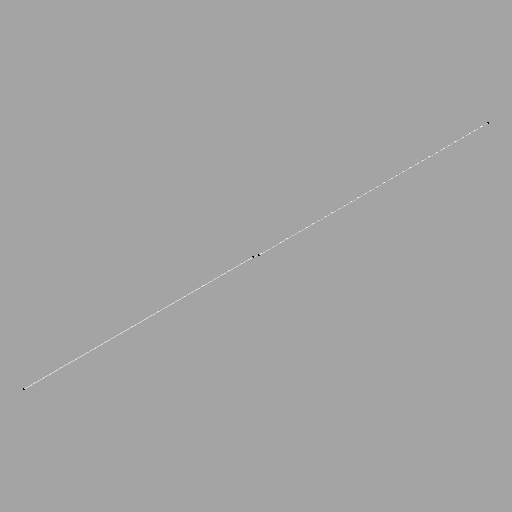
# Autodesk Inventor part: Cell_Ribbon
Saved by Autodesk Inventor 2026.2 (Build 302298000, 298)
## iProperties
Created: 2026-11-08
Part Number: Cell_Ribbon
Material: Generic
Document SubType Name: Modeling
Designer: Jacob
Density: 1 g/cm^3
Appearance: Default
Cu_Dia: 0.270 mm
Coating_Thickness: 0.015 mm
Wire_OD: 0.300 mm
Cell_Gap: 1.400 mm
Ribbon_Pad_Length: 83.170 mm
Ribbon_Overhang: 8.000 mm
Author: Jacob
Autodesk Inventor part; units mm, degrees
ref_plane "YZ Plane" through (0, 0, 0) normal (1, 0, 0) x (0, 1, 0)
ref_plane "XZ Plane" through (0, 0, 0) normal (0, 1, 0) x (-1, 0, 0)
sketch "Sketch1" plane through (0, 0, 0) normal (1, 0, 0) x (0, 1, 0)
  line L0 (-0.15, -83.87) -> (-0.15, -0.95)
  line L1 (-0.1385, -0.8591) -> (0.3035, 0.8591)
  line L2 (0.315, 0.95) -> (0.315, 83.87)
  arc A0 (-0.1385, -0.8591) -> (-0.15, -0.95) centre (0.215, -0.95) ccw
  arc A1 (0.3035, 0.8591) -> (0.315, 0.95) centre (-0.05, 0.95) ccw
  point P0 (0, 0)
  dimension "d0" = 0.15
  dimension "d1" = 0.315
  dimension "d2" = 83.87
  dimension "d3" = 83.87
  dimension "d4" = 0.95
  dimension "d5" = 0.95
  constraints: 6 end point, 4 point on circle, 4 tangent, 2 centre point, 2 vertical
  measures "d0" horizontal distance of point (0, 0) L0.start
  measures "d1" horizontal distance of point (0, 0) L2.end
  measures "d2" distance of point (0, 0) L0.start
  measures "d3" vertical distance of point (0, 0) L2.end
  measures "d4" vertical distance of point (0, 0) L0.end
  measures "d5" vertical distance of point (0, 0) L2.start
ref_plane "Work Plane1" through (0, -0.15, -83.87) normal (0, 0, 1) x (1, 0, 0)
sketch "Sketch2" plane through (0, -0.15, -83.87) normal (0, 0, 1) x (1, 0, 0)
  circle A0 centre (0, 0) radius 0.135
  dimension "d6" = 0.27
  constraints: 1 centre point
  measures "d6" diameter of A0
sweep "Copper_Core_Sweep" add profiles "Sketch2" path "Sketch1" path curves L0 A0 L1 A1 L2
sketch "Sketch3" plane through (0, -0.15, -83.87) normal (0, 0, 1) x (1, 0, 0)
  circle A0 centre (0, 0) radius 0.135
  circle A1 centre (0, 0) radius 0.15
  dimension "d9" = 0.27
  dimension "d10" = 0.3
  constraints: 2 centre point
  measures "d9" diameter of A0
  measures "d10" diameter of A1
sweep "SnPb_Coating_Sweep" add profiles "Sketch3" path "Sketch1" separate body path curves L0 A0 L1 A1 L2 contours A0 | A1
equation "\"d0\" = 0.5 * Wire_OD"
equation "\"d1\" = Cell_Thickness + 0.5 * Wire_OD"
equation "\"d2\" = Ribbon_Pad_Length + 0.5 * Cell_Gap"
equation "\"d3\" = Ribbon_Pad_Length + 0.5 * Cell_Gap"
equation "\"d6\" = Cu_Dia"
equation "\"d9\" = Cu_Dia"
equation "\"d10\" = Wire_OD"
equation "\"Cu_Dia\" = 0.27"
equation "\"Coating_Thickness\" = 0.015"
equation "\"Wire_OD\" = Cu_Dia + 2 * Coating_Thickness"
equation "\"Cell_Gap\" = 1.4"
equation "\"Ribbon_Pad_Length\" = 83.17"
equation "\"Ribbon_Overhang\" = 8"
equation "\"Cell_Thickness\" = 0.165"
